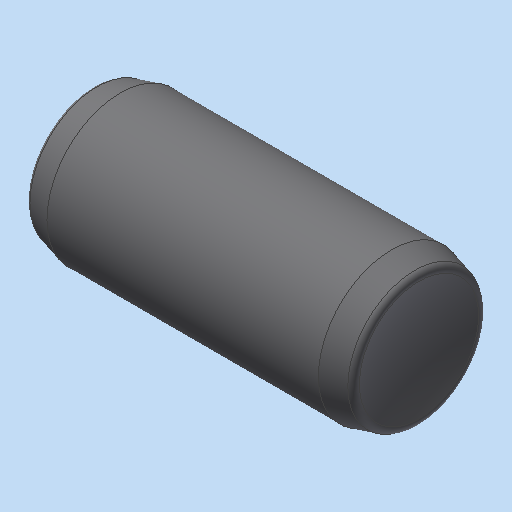
# Autodesk Inventor part: Zylinderstift_DIN_EN_ISO_8734___8x18
Saved by Autodesk Inventor 2023.3 (Build 273359000, 359)
## iProperties
Shininess: 64.0
Length Units: 11269
Angle Units: 11279
Time Units: 11290
Mass Units: 11283
Length Display Precision: 3
Angle Display Precision: 2
Compacted: True
Part Number: Zylinderstift_DIN_EN_ISO_8734___8x18
Document SubType Name: Modeling
Created: 2004-04-23
Description: =<RBPARTNOTITLE2>
Vendor: NORM8
Designer: C.Fischer
Manufacturer: Standard
Standards Organization: Custom
Density: 7.85 g/cm^3
Material: xStahl_AnP_Dummymaterial
Appearance: Stahl - normal AnP
Mass: 6.75958 g
Surface Area: 5.26065 cm^2
Volume: 0.861093 cm^3
DOC_ID: 5 F45 Zylinderstift_DIN_EN_ISO_8734___8x18
Control State: 0
Master: False
Checked Out: False
CNS_NB: Zylinderstift DIN EN ISO 8734 - 8x18
CNS_NN: DIN EN ISO 8734
CNS_NT: Zylinderstifte, aus gehaertetem Stahl und martensitischem nichtrostendem Stahl
CNS_NBSYN: Zylinderstift DIN EN ISO 8734 - $NENN.
CNS_LINA: Zylinderstift DIN EN ISO 8734 - 8x18
CNS_D: 8.000
CNS_L: 18.000
CNS_A: 1.600
CNS_NENN: 8x18
CNS_KT: DUMMY
PSOL_IDENT_0: {C:\partsolutions\data\23d-libs\bosch_bamberg\stifte\scherstifte\din_en_iso_8734.prj},164 {VTYP=3D},
PSOL_IDENT_1: {NB=Zylinderstift DIN EN ISO 8734 - 8x18},{NN=DIN EN ISO 8734},{DATE=26.11.2003},{GEOMDATE=26.11.200
PSOL_IDENT_2: 3},{VERSION=v1},{LINEID=910},{LINESUBID=-1},{WBVAR=}  {NB=Zylinderstift DIN EN ISO 8734 - 8x18},{LIN
PSOL_IDENT_3: A=Zylinderstift DIN EN ISO 8734 - 8x18},{KT=DUMMY},{IDNR=},{D=8.000},{L=18.000},{A=1.600},{NENN=8x18
PSOL_IDENT_4: }
DEF_STKID: T18575
Bezeichnung1: Zylinderstift DIN EN ISO 8734 - 8x18
Bezeichnung2: Zylinderstifte, aus gehaertetem Stahl u
RBPARTNOTITLE1: Parallel pins of hardened and martensitic stainless steel
RBPARTNOTITLE2: Zylinderstifte, aus gehaertetem Stahl und martensitischem nichtrostendem Stahl
RBDRAWINGMISSINGSPEC: --
AnP_Kategorie: 4
RBPARTMADEOF: ISO 8734 - 8x18 - A - St
Density: 0.0
Volumn: 0.0
Area: 0.0
PropertySet Name: Model Information
Title: Zylinderstift DIN EN ISO 8734 - 8x18
Author: C.Fischer
Keywords: =<RBPARTMADEOF>
Comments: =<RBSURFACE2>
Revision Number: 01
Autodesk Inventor part; units mm, degrees
sketch "Sketch_1" plane through (0, 0, 0) normal (0, 0, 1) x (1, 0, 0)
  line L0 (18, 0) -> (0, 0)
  arc A0 (0.64, 0) -> (0.1128, 3.2504) centre (-9.6441, 0) ccw
  arc A1 (0.3336, 3.6607) -> (0.1128, 3.2504) centre (0.4164, 3.3516) ccw
  line L1 (0.3336, 3.6607) -> (1.6, 4)
  line L2 (1.6, 4) -> (16.4, 4)
  line L3 (16.4, 4) -> (17.6664, 3.6607)
  arc A2 (17.8872, 3.2504) -> (17.6664, 3.6607) centre (17.5836, 3.3516) ccw
  arc A3 (17.8872, 3.2504) -> (17.36, 0) centre (27.6441, 0) ccw
  line L4 (17.36, 0) -> (0.64, 0)
  constraints: 10 end point, 8 point on circle, 4 centre point
revolve "Revolution1" add sketch "Sketch_1" angle 360 about axis through (18, 0, 0) along (1, 0, 0)
ref_plane "IP2_XY" through (0, 0, 0) normal (1, 0, 0) x (0, 0, -1)
ref_plane "IP2_YZ" through (0, 0, 0) normal (0, 0, -1) x (0, 1, 0)
ref_plane "IP1_XY" through (9, 0, 0) normal (1, 0, 0) x (0, 0, -1)
ref_plane "IP1_YZ" through (9, 0, 0) normal (0, 0, -1) x (0, 1, 0)
ref_plane "IP3_XY" through (18, 0, 0) normal (1, 0, 0) x (0, 0, -1)
ref_plane "IP3_YZ" through (18, 0, 0) normal (0, 0, -1) x (0, 1, 0)
